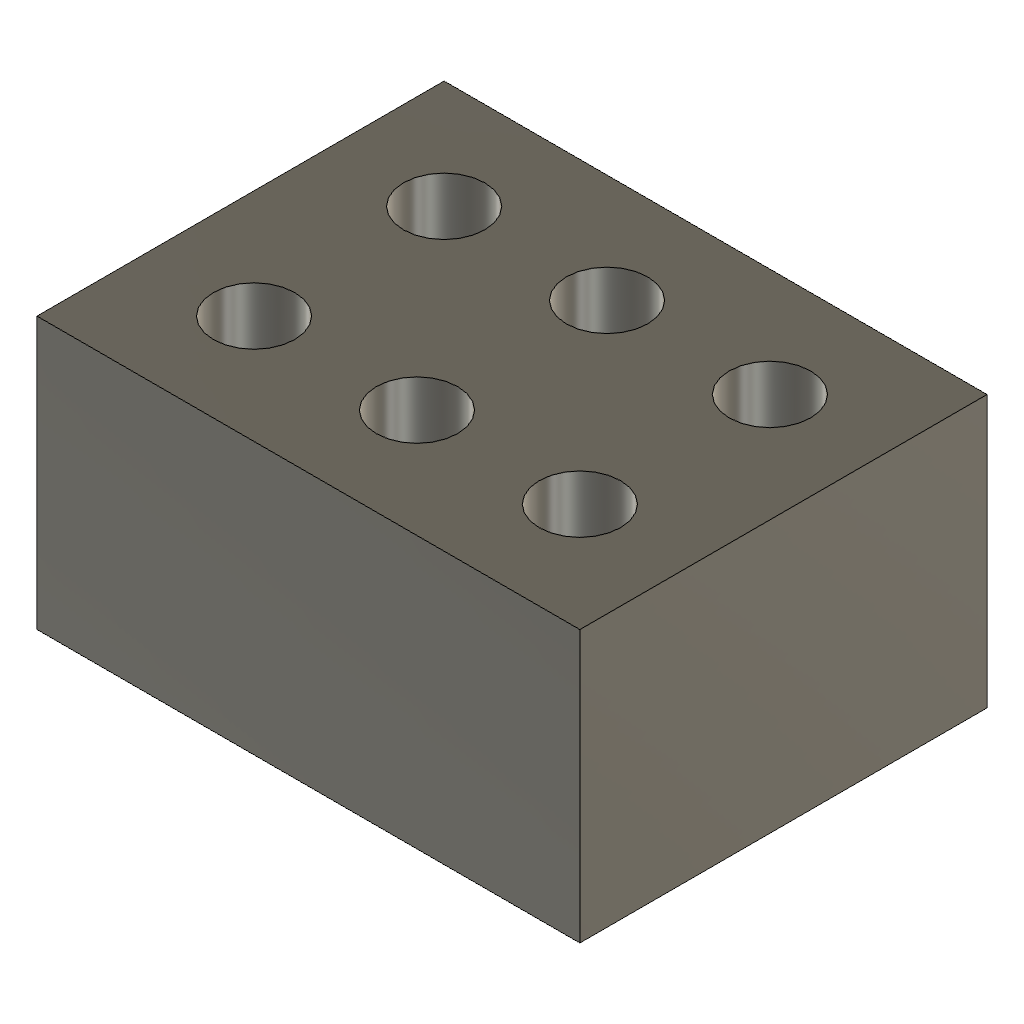
RectPattern (Autodesk Fusion 360 design; units mm, degrees)
part number: 2026-11-12-11-46-36-693
Autodesk Fusion 360 part; units mm, degrees
sketch "Base sketch" plane through (0, 0, 0) normal (0, 0, 1) x (1, 0, 0)
  line L0 (0, 0) -> (40, 0)
  line L1 (40, 0) -> (40, 30)
  line L2 (40, 30) -> (0, 30)
  line L3 (0, 30) -> (0, 0)
extrude "Base extrude" add sketch "Base sketch" along normal blind 20
sketch "Pocket sketch" plane through (0, 0, 0) normal (0, 0, 1) x (1, 0, 0)
  circle A0 centre (8, 8) radius 3
extrude "Pocket extrude" cut sketch "Pocket sketch" along normal blind 20
pattern_linear "Pocket grid" count 3 spacing 12 along (1, 0, 0) count 2 spacing 14 along (0, 1, 0) of "Pocket extrude"
